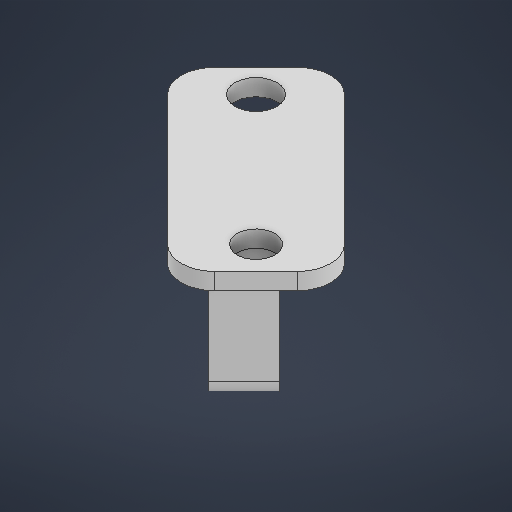
# Autodesk Inventor part: bearing_support
Saved by Autodesk Inventor 2027.1 (Build 311270010, 270A)
## iProperties
Created: 2026-11-04
Part Number: bearing_support
Material: Ogólny
Document SubType Name: Modeling
Designer: User
Density: 1 g/cm^3
Appearance: Domyślna
Author: User
Autodesk Inventor part; units mm, degrees
ref_plane "YZ Plane" through (0, 0, 0) normal (1, 0, 0) x (0, 1, 0)
ref_plane "XZ Plane" through (0, 0, 0) normal (0, 1, 0) x (-1, 0, 0)
ref_plane "XY Plane" through (0, 0, 0) normal (0, 0, 1) x (1, 0, 0)
sketch "Szkic1" plane through (0, 0, 0) normal (0, 1, 0) x (-1, 0, 0)
  line L0 (17.5311, 45.5011) -> (38.7443, 24.2879)
  line L1 (38.7443, 24.2879) -> (28.1377, 13.6813)
  line L2 (28.1377, 13.6813) -> (6.9245, 34.8945)
  line L3 (6.9245, 34.8945) -> (17.5311, 45.5011)
  line L4 (17.5311, 45.5011) -> (28.1377, 13.6813) construction
  line L5 (38.7443, 24.2879) -> (6.9245, 34.8945) construction
  line L6 (17.5311, 45.5011) -> (47.5311, 45.5011) construction
  line L7 (12.2278, 40.1978) -> (15.0562, 37.3694)
  line L8 (12.2278, 40.1978) -> (16.2278, 40.1978) construction
  circle A0 centre (15.0562, 37.3694) radius 1.5
  circle A1 centre (15.0562, 37.3694) radius 2.25
  circle A2 centre (30.6126, 21.813) radius 2.25
  circle A3 centre (30.6126, 21.813) radius 2.5
  dimension "d1" = 30
  dimension "d2" = 45
  dimension "d3" = 15
  dimension "d4" = 4
  dimension "d5" = 45
  dimension "d6" = 3
  dimension "d7" = 4.5
  dimension "d8" = 4.5
  constraints: 18 end point, 4 centre point, 3 coincident, 2 equal length, 2 horizontal, 2 parallel, 1 midpoint, 1 perpendicular
  measures "d1" distance of L6.start L0.end
  measures "d2" angle of L0 L6
  measures "d3" distance of L0.end L4.end
  measures "d4" distance of L7.start L7.end
  measures "d5" angle of L7 L8
  measures "d6" diameter of A0
  measures "d7" diameter of A1
  measures "d8" diameter of A2
extrude "Wyciągnięcie proste1" add sketch "Szkic1" against normal blind 2 contours L0 L1 L2 L3
fillet "Zaokrąglenie1" radius 4 4 edges at (-17.5311, -1, 45.5011) (-6.9245, -1, 34.8945) (-38.7443, -1, 24.2879) (-28.1377, -1, 13.6813)
sketch "Szkic2" plane through (0, -2, 0) normal (0, -1, 0) x (1, 0, 0)
  line L0 (-25.3093, 16.5097) -> (-9.7529, 32.0661) construction
  line L1 (-17.5311, 24.2879) -> (-28.1377, 34.8945) construction
  line L2 (-20.3595, 42.6727) -> (-35.9159, 27.1163) construction
  circle A0 centre (-30.6126, 21.813) radius 2.5 construction
  line L3 (-30.6126, 21.813) -> (-15.0068, 37.4188) construction
  line L4 (-27.4059, 22.1913) -> (-15.3851, 34.2121)
  line L5 (-15.3851, 34.2121) -> (-18.2135, 37.0405)
  line L6 (-18.2135, 37.0405) -> (-30.2343, 25.0197)
  line L7 (-30.2343, 25.0197) -> (-27.4059, 22.1913)
  line L8 (-27.4059, 22.1913) -> (-18.2135, 37.0405) construction
  line L9 (-15.3851, 34.2121) -> (-30.2343, 25.0197) construction
  point P0 (0, 0)
  point P1 (-22.8097, 29.6159)
  dimension "d12" = 17
  dimension "d13" = 4
  dimension "d14" = 90
  constraints: 16 end point, 5 midpoint, 2 parallel, 2 perpendicular
  measures "d12" distance of L4.start L4.end
  measures "d13" distance of L5.end L4.end
  measures "d14" angle of L1 L6
extrude "Wyciągnięcie proste2" add sketch "Szkic2" along normal blind 16
sketch "Szkic3" plane through (-15.3851, -18, 34.2121) normal (0.7071068, 0, -0.7071068) x (-0.7071068, 0, -0.7071068)
  line L0 (17, 0) -> (0, 0) projected
  line L1 (-6.4651, 18) -> (-6.4651, 16) projected
  line L2 (19.5349, 16) -> (-2.4651, 16) projected
  line L3 (0, 16) -> (17, 16) projected
  line L4 (0, 16) -> (0, 0) projected
  line L5 (17, 0) -> (0, 0) projected
  line L6 (17, 16) -> (17, 0) projected
  line L7 (0, 16) -> (17, 0) construction
  line L8 (0, 0) -> (17, 16) construction
  circle A0 centre (8.5, 8) radius 7.7
  point P0 (23.5349, 16)
  dimension "d37" = 15.4
  constraints: 4 end point, 1 centre point, 1 midpoint
  measures "d37" diameter of A0
extrude "Wyciągnięcie proste5" cut sketch "Szkic3" against normal blind 16 contours A0
fillet "Zaokrąglenie3" radius 2 2 edges at (-28.8201, -18, 23.6055) (-16.7993, -18, 35.6263)
sketch "Szkic4" plane through (-18.2135, -16, 37.0405) normal (-0.7071068, 0, 0.7071068) x (0.7071068, 0, 0.7071068)
  arc A0 (-2, -2) -> (0, 0) centre (-2, 0) ccw projected
  line L0 (0, 14) -> (0, 0) projected
  line L1 (-17, 14) -> (0, 14) projected
  line L2 (-17, 14) -> (-17, 0) projected
  arc A1 (-17, 0) -> (-15, -2) centre (-15, 0) ccw projected
  line L3 (-2, -2) -> (-15, -2) projected
  circle A2 centre (-8.5, 6) radius 7.7 projected
  point P0 (-13.3127, 16)
extrude "Wyciągnięcie proste6" add sketch "Szkic4" along normal blind 2 contours L3 A1 L2 L1 L0 A0 | A2
